Autodesk Fusion 360 part; units mm, degrees
(part 2 of 3)
ref_plane "WorkPlane161" through (-25.1, 0, 0) normal (1, 0, 0) x (0, 1, 0)
sketch "ESP service plug clearance 14 x 8 PHOTO ESTIMATE" plane through (-25.1, 0, 0) normal (1, 0, 0) x (0, 0, -1)
  line L0 (-13, -23) -> (-13, -9)
  line L1 (-13, -9) -> (-21, -9)
  line L2 (-21, -9) -> (-21, -23)
  line L3 (-21, -23) -> (-13, -23)
ref_plane "WorkPlane162" through (51.9632, 0, 0) normal (1, 0, 0) x (0, 1, 0)
sketch "Type C PCB edge slit 17.9 x 2.0 PHOTO RULER" plane through (51.9632, 0, 0) normal (1, 0, 0) x (0, 0, -1)
  line L0 (-9.3, -27.19) -> (-9.3, -9.29)
  line L1 (-9.3, -9.29) -> (-11.3, -9.29)
  line L2 (-11.3, -9.29) -> (-11.3, -27.19)
  line L3 (-11.3, -27.19) -> (-9.3, -27.19)
ref_plane "WorkPlane163" through (51.9632, 0, 0) normal (1, 0, 0) x (0, 1, 0)
sketch "Type C metal clearance 9.4 x 3.4 PHOTO RULER" plane through (51.9632, 0, 0) normal (1, 0, 0) x (0, 0, -1)
  line L0 (-6.3, -22.34) -> (-6.3, -14.14)
  line L1 (-6.3, -14.14) -> (-6.9, -13.54)
  line L2 (-6.9, -13.54) -> (-9.1, -13.54)
  line L3 (-9.1, -13.54) -> (-9.7, -14.14)
  line L4 (-9.7, -14.14) -> (-9.7, -22.34)
  line L5 (-9.7, -22.34) -> (-9.1, -22.94)
  line L6 (-9.1, -22.94) -> (-6.9, -22.94)
  line L7 (-6.9, -22.94) -> (-6.3, -22.34)
ref_plane "WorkPlane164" through (-25.1, 0, 0) normal (1, 0, 0) x (0, 1, 0)
sketch "ESP32 PCB edge slit 28.4 x 2.0 PHOTO RULER" plane through (-25.1, 0, 0) normal (1, 0, 0) x (0, 0, -1)
  line L0 (-15.9, -32.44) -> (-15.9, -4.04)
  line L1 (-15.9, -4.04) -> (-17.9, -4.04)
  line L2 (-17.9, -4.04) -> (-17.9, -32.44)
  line L3 (-17.9, -32.44) -> (-15.9, -32.44)
ref_plane "WorkPlane165" through (-25.1, 0, 0) normal (1, 0, 0) x (0, 1, 0)
sketch "ESP micro USB recessed plug access 10.4 x 4.6" plane through (-25.1, 0, 0) normal (1, 0, 0) x (0, 0, -1)
  line L0 (-16.8, -22.74) -> (-16.8, -13.74)
  line L1 (-16.8, -13.74) -> (-17.5, -13.04)
  line L2 (-17.5, -13.04) -> (-20.7, -13.04)
  line L3 (-20.7, -13.04) -> (-21.4, -13.74)
  line L4 (-21.4, -13.74) -> (-21.4, -22.74)
  line L5 (-21.4, -22.74) -> (-20.7, -23.44)
  line L6 (-20.7, -23.44) -> (-17.5, -23.44)
  line L7 (-17.5, -23.44) -> (-16.8, -22.74)
ref_plane "WorkPlane166" through (0, 0, 9.5) normal (0, 0, 1) x (1, 0, 0)
sketch "REF_DO_NOT_PRINT Charger PCB 17.5 wide PHOTO RULER" plane through (0, 0, 9.5) normal (0, 0, 1) x (1, 0, 0)
  line L0 (23.4316, -26.99) -> (50.4316, -26.99)
  line L1 (50.4316, -26.99) -> (50.4316, -9.49)
  line L2 (50.4316, -9.49) -> (23.4316, -9.49)
  line L3 (23.4316, -9.49) -> (23.4316, -26.99)
extrude "REF_DO_NOT_PRINT Charger PCB 17.5 wide PHOTO RULER (1)" add sketch "REF_DO_NOT_PRINT Charger PCB 17.5 wide PHOTO RULER" along normal blind 1.6 separate body makes body 7
ref_plane "WorkPlane167" through (0, 0, 6.5) normal (0, 0, 1) x (1, 0, 0)
sketch "REF_DO_NOT_PRINT Type C shell 9 x 3 PHOTO ESTIMATE" plane through (0, 0, 6.5) normal (0, 0, 1) x (1, 0, 0)
  line L0 (44.4316, -22.74) -> (52.4316, -22.74)
  line L1 (52.4316, -22.74) -> (52.4316, -13.74)
  line L2 (52.4316, -13.74) -> (44.4316, -13.74)
  line L3 (44.4316, -13.74) -> (44.4316, -22.74)
extrude "REF_DO_NOT_PRINT Type C shell 9 x 3 PHOTO ESTIMATE (1)" add sketch "REF_DO_NOT_PRINT Type C shell 9 x 3 PHOTO ESTIMATE" along normal blind 3 separate body makes body 8
ref_plane "WorkPlane168" through (0, 0, 16.1) normal (0, 0, 1) x (1, 0, 0)
sketch "REF_DO_NOT_PRINT ESP32 PCB 28 wide PHOTO RULER" plane through (0, 0, 16.1) normal (0, 0, 1) x (1, 0, 0)
  line L0 (-16, -32.24) -> (36, -32.24)
  line L1 (36, -32.24) -> (36, -4.24)
  line L2 (36, -4.24) -> (-16, -4.24)
  line L3 (-16, -4.24) -> (-16, -32.24)
extrude "REF_DO_NOT_PRINT ESP32 PCB 28 wide PHOTO RULER (1)" add sketch "REF_DO_NOT_PRINT ESP32 PCB 28 wide PHOTO RULER" along normal blind 1.6 separate body makes body 9
ref_plane "WorkPlane169" through (0, 0, 17.6) normal (0, 0, 1) x (1, 0, 0)
sketch "REF_DO_NOT_PRINT ESP micro USB shell 7.8 x 3 PHOTO ESTIMATE" plane through (0, 0, 17.6) normal (0, 0, 1) x (1, 0, 0)
  line L0 (-17.5, -22.14) -> (-11, -22.14)
  line L1 (-11, -22.14) -> (-11, -14.34)
  line L2 (-11, -14.34) -> (-17.5, -14.34)
  line L3 (-17.5, -14.34) -> (-17.5, -22.14)
extrude "REF_DO_NOT_PRINT ESP micro USB shell 7.8 x 3 PHOTO ESTIMATE (1)" add sketch "REF_DO_NOT_PRINT ESP micro USB shell 7.8 x 3 PHOTO ESTIMATE" along normal blind 3 separate body makes body 10
ref_plane "WorkPlane170" through (0, 0, 17.7) normal (0, 0, 1) x (1, 0, 0)
sketch "REF_DO_NOT_PRINT ESP32 shield envelope PHOTO ESTIMATE" plane through (0, 0, 17.7) normal (0, 0, 1) x (1, 0, 0)
  line L0 (4, -29.74) -> (28, -29.74)
  line L1 (28, -29.74) -> (28, -6.74)
  line L2 (28, -6.74) -> (4, -6.74)
  line L3 (4, -6.74) -> (4, -29.74)
extrude "REF_DO_NOT_PRINT ESP32 shield envelope PHOTO ESTIMATE (1)" add sketch "REF_DO_NOT_PRINT ESP32 shield envelope PHOTO ESTIMATE" along normal blind 3.8 separate body makes body 11
ref_plane "WorkPlane171" through (51.9632, 0, 0) normal (1, 0, 0) x (0, 1, 0)
sketch "Type C metal clearance 9.4 x 3.4 corner clearance" plane through (51.9632, 0, 0) normal (1, 0, 0) x (0, 0, -1)
  line L0 (-6.3, -22.64) -> (-6.3, -13.84)
  line L1 (-6.3, -13.84) -> (-6.6, -13.54)
  line L2 (-6.6, -13.54) -> (-9.4, -13.54)
  line L3 (-9.4, -13.54) -> (-9.7, -13.84)
  line L4 (-9.7, -13.84) -> (-9.7, -22.64)
  line L5 (-9.7, -22.64) -> (-9.4, -22.94)
  line L6 (-9.4, -22.94) -> (-6.6, -22.94)
  line L7 (-6.6, -22.94) -> (-6.3, -22.64)
ref_plane "WorkPlane172" through (0, 0, 27.3) normal (0, 0, 1) x (1, 0, 0)
sketch "REF_AUDIT Radio PCB 45 x 16 PHOTO APPROX" plane through (0, 0, 27.3) normal (0, 0, 1) x (1, 0, 0)
  line L0 (3.4316, 9) -> (48.4316, 9)
  line L1 (48.4316, 9) -> (48.4316, 25)
  line L2 (48.4316, 25) -> (3.4316, 25)
  line L3 (3.4316, 25) -> (3.4316, 9)
ref_plane "WorkPlane173" through (0, 0, 13.1) normal (0, 0, 1) x (1, 0, 0)
sketch "REF_AUDIT White harness connector PHOTO APPROX" plane through (0, 0, 13.1) normal (0, 0, 1) x (1, 0, 0)
  line L0 (-23.1, -22) -> (-16, -22)
  line L1 (-16, -22) -> (-16, 13)
  line L2 (-16, 13) -> (-23.1, 13)
  line L3 (-23.1, 13) -> (-23.1, -22)
ref_plane "WorkPlane174" through (0, 0, 39.1) normal (0, 0, 1) x (1, 0, 0)
sketch "Key aperture corrected layout 1" plane through (0, 0, 39.1) normal (0, 0, 1) x (1, 0, 0)
  circle A0 centre (-8, -19.5) radius 2.3
extrude "Key aperture corrected layout 1 (1)" cut sketch "Key aperture corrected layout 1" against normal blind 1.6 bodies 2
ref_plane "WorkPlane175" through (0, 0, 33.1) normal (0, 0, 1) x (1, 0, 0)
sketch "Button 1 stem layout corrected" plane through (0, 0, 33.1) normal (0, 0, 1) x (1, 0, 0)
  circle A0 centre (-8, -19.5) radius 1.6
extrude "Button 1 stem layout corrected (1)" add sketch "Button 1 stem layout corrected" along normal blind 6.4 separate body makes body 12
ref_plane "WorkPlane176" through (0, 0, 36.9) normal (0, 0, 1) x (1, 0, 0)
sketch "Button 1 retention flange (1)" plane through (0, 0, 36.9) normal (0, 0, 1) x (1, 0, 0)
  circle A0 centre (-8, -19.5) radius 2.8
extrude "Button 1 retention flange (2)" add sketch "Button 1 retention flange (1)" along normal blind 0.6 bodies 12
ref_plane "WorkPlane177" through (0, 0, 36.1) normal (0, 0, 1) x (1, 0, 0)
sketch "Button printable flange taper corrected" plane through (0, 0, 36.1) normal (0, 0, 1) x (1, 0, 0)
  circle A0 centre (-8, -19.5) radius 1.6
extrude "Button 45 degree shoulder corrected" add sketch "Button printable flange taper corrected" along normal blind 1.2 draft 45 bodies 12
ref_plane "WorkPlane178" through (0, 0, 29.6) normal (0, 0, 1) x (1, 0, 0)
sketch "REF_DO_NOT_PRINT Tact switch corrected 1" plane through (0, 0, 29.6) normal (0, 0, 1) x (1, 0, 0)
  circle A0 centre (-8, -19.5) radius 1.75
extrude "REF_DO_NOT_PRINT Tact switch corrected 1 (1)" add sketch "REF_DO_NOT_PRINT Tact switch corrected 1" along normal blind 3.5 separate body makes body 13
ref_plane "WorkPlane179" through (0, 0, 39.1) normal (0, 0, 1) x (1, 0, 0)
sketch "Key aperture corrected layout 2" plane through (0, 0, 39.1) normal (0, 0, 1) x (1, 0, 0)
  circle A0 centre (-8, -11.88) radius 2.3
extrude "Key aperture corrected layout 2 (1)" cut sketch "Key aperture corrected layout 2" against normal blind 1.6 bodies 2
ref_plane "WorkPlane180" through (0, 0, 33.1) normal (0, 0, 1) x (1, 0, 0)
sketch "Button 2 stem layout corrected" plane through (0, 0, 33.1) normal (0, 0, 1) x (1, 0, 0)
  circle A0 centre (-8, -11.88) radius 1.6
extrude "Button 2 stem layout corrected (1)" add sketch "Button 2 stem layout corrected" along normal blind 6.4 separate body makes body 14
ref_plane "WorkPlane181" through (0, 0, 36.9) normal (0, 0, 1) x (1, 0, 0)
sketch "Button 2 retention flange (1)" plane through (0, 0, 36.9) normal (0, 0, 1) x (1, 0, 0)
  circle A0 centre (-8, -11.88) radius 2.8
extrude "Button 2 retention flange (2)" add sketch "Button 2 retention flange (1)" along normal blind 0.6 bodies 14
ref_plane "WorkPlane182" through (0, 0, 36.1) normal (0, 0, 1) x (1, 0, 0)
sketch "Button printable flange taper corrected (1)" plane through (0, 0, 36.1) normal (0, 0, 1) x (1, 0, 0)
  circle A0 centre (-8, -11.88) radius 1.6
extrude "Button 45 degree shoulder corrected (1)" add sketch "Button printable flange taper corrected (1)" along normal blind 1.2 draft 45 bodies 14
ref_plane "WorkPlane183" through (0, 0, 29.6) normal (0, 0, 1) x (1, 0, 0)
sketch "REF_DO_NOT_PRINT Tact switch corrected 2" plane through (0, 0, 29.6) normal (0, 0, 1) x (1, 0, 0)
  circle A0 centre (-8, -11.88) radius 1.75
extrude "REF_DO_NOT_PRINT Tact switch corrected 2 (1)" add sketch "REF_DO_NOT_PRINT Tact switch corrected 2" along normal blind 3.5 separate body makes body 15
ref_plane "WorkPlane184" through (0, 0, 39.1) normal (0, 0, 1) x (1, 0, 0)
sketch "Key aperture corrected layout 3" plane through (0, 0, 39.1) normal (0, 0, 1) x (1, 0, 0)
  circle A0 centre (-8, -4.26) radius 2.3
extrude "Key aperture corrected layout 3 (1)" cut sketch "Key aperture corrected layout 3" against normal blind 1.6 bodies 2
ref_plane "WorkPlane185" through (0, 0, 33.1) normal (0, 0, 1) x (1, 0, 0)
sketch "Button 3 stem layout corrected" plane through (0, 0, 33.1) normal (0, 0, 1) x (1, 0, 0)
  circle A0 centre (-8, -4.26) radius 1.6
extrude "Button 3 stem layout corrected (1)" add sketch "Button 3 stem layout corrected" along normal blind 6.4 separate body makes body 16
ref_plane "WorkPlane186" through (0, 0, 36.9) normal (0, 0, 1) x (1, 0, 0)
sketch "Button 3 retention flange (1)" plane through (0, 0, 36.9) normal (0, 0, 1) x (1, 0, 0)
  circle A0 centre (-8, -4.26) radius 2.8
extrude "Button 3 retention flange (2)" add sketch "Button 3 retention flange (1)" along normal blind 0.6 bodies 16
ref_plane "WorkPlane187" through (0, 0, 36.1) normal (0, 0, 1) x (1, 0, 0)
sketch "Button printable flange taper corrected (2)" plane through (0, 0, 36.1) normal (0, 0, 1) x (1, 0, 0)
  circle A0 centre (-8, -4.26) radius 1.6
extrude "Button 45 degree shoulder corrected (2)" add sketch "Button printable flange taper corrected (2)" along normal blind 1.2 draft 45 bodies 16
ref_plane "WorkPlane188" through (0, 0, 29.6) normal (0, 0, 1) x (1, 0, 0)
sketch "REF_DO_NOT_PRINT Tact switch corrected 3" plane through (0, 0, 29.6) normal (0, 0, 1) x (1, 0, 0)
  circle A0 centre (-8, -4.26) radius 1.75
extrude "REF_DO_NOT_PRINT Tact switch corrected 3 (1)" add sketch "REF_DO_NOT_PRINT Tact switch corrected 3" along normal blind 3.5 separate body makes body 17
ref_plane "WorkPlane189" through (0, 0, 39.1) normal (0, 0, 1) x (1, 0, 0)
sketch "Key aperture corrected layout 4" plane through (0, 0, 39.1) normal (0, 0, 1) x (1, 0, 0)
  circle A0 centre (-8, 3.36) radius 2.3
extrude "Key aperture corrected layout 4 (1)" cut sketch "Key aperture corrected layout 4" against normal blind 1.6 bodies 2
ref_plane "WorkPlane190" through (0, 0, 33.1) normal (0, 0, 1) x (1, 0, 0)
sketch "Button 4 stem layout corrected" plane through (0, 0, 33.1) normal (0, 0, 1) x (1, 0, 0)
  circle A0 centre (-8, 3.36) radius 1.6
extrude "Button 4 stem layout corrected (1)" add sketch "Button 4 stem layout corrected" along normal blind 6.4 separate body makes body 18
ref_plane "WorkPlane191" through (0, 0, 36.9) normal (0, 0, 1) x (1, 0, 0)
sketch "Button 4 retention flange (1)" plane through (0, 0, 36.9) normal (0, 0, 1) x (1, 0, 0)
  circle A0 centre (-8, 3.36) radius 2.8
extrude "Button 4 retention flange (2)" add sketch "Button 4 retention flange (1)" along normal blind 0.6 bodies 18
ref_plane "WorkPlane192" through (0, 0, 36.1) normal (0, 0, 1) x (1, 0, 0)
sketch "Button printable flange taper corrected (3)" plane through (0, 0, 36.1) normal (0, 0, 1) x (1, 0, 0)
  circle A0 centre (-8, 3.36) radius 1.6
extrude "Button 45 degree shoulder corrected (3)" add sketch "Button printable flange taper corrected (3)" along normal blind 1.2 draft 45 bodies 18
ref_plane "WorkPlane193" through (0, 0, 29.6) normal (0, 0, 1) x (1, 0, 0)
sketch "REF_DO_NOT_PRINT Tact switch corrected 4" plane through (0, 0, 29.6) normal (0, 0, 1) x (1, 0, 0)
  circle A0 centre (-8, 3.36) radius 1.75
extrude "REF_DO_NOT_PRINT Tact switch corrected 4 (1)" add sketch "REF_DO_NOT_PRINT Tact switch corrected 4" along normal blind 3.5 separate body makes body 19
ref_plane "WorkPlane194" through (0, 0, 39.1) normal (0, 0, 1) x (1, 0, 0)
sketch "Key aperture corrected layout 5" plane through (0, 0, 39.1) normal (0, 0, 1) x (1, 0, 0)
  circle A0 centre (-0.38, -19.5) radius 2.3
extrude "Key aperture corrected layout 5 (1)" cut sketch "Key aperture corrected layout 5" against normal blind 1.6 bodies 2
ref_plane "WorkPlane195" through (0, 0, 33.1) normal (0, 0, 1) x (1, 0, 0)
sketch "Button 5 stem layout corrected" plane through (0, 0, 33.1) normal (0, 0, 1) x (1, 0, 0)
  circle A0 centre (-0.38, -19.5) radius 1.6
extrude "Button 5 stem layout corrected (1)" add sketch "Button 5 stem layout corrected" along normal blind 6.4 separate body makes body 20
ref_plane "WorkPlane196" through (0, 0, 36.9) normal (0, 0, 1) x (1, 0, 0)
sketch "Button 5 retention flange (1)" plane through (0, 0, 36.9) normal (0, 0, 1) x (1, 0, 0)
  circle A0 centre (-0.38, -19.5) radius 2.8
extrude "Button 5 retention flange (2)" add sketch "Button 5 retention flange (1)" along normal blind 0.6 bodies 20
ref_plane "WorkPlane197" through (0, 0, 36.1) normal (0, 0, 1) x (1, 0, 0)
sketch "Button printable flange taper corrected (4)" plane through (0, 0, 36.1) normal (0, 0, 1) x (1, 0, 0)
  circle A0 centre (-0.38, -19.5) radius 1.6
extrude "Button 45 degree shoulder corrected (4)" add sketch "Button printable flange taper corrected (4)" along normal blind 1.2 draft 45 bodies 20
ref_plane "WorkPlane198" through (0, 0, 29.6) normal (0, 0, 1) x (1, 0, 0)
sketch "REF_DO_NOT_PRINT Tact switch corrected 5" plane through (0, 0, 29.6) normal (0, 0, 1) x (1, 0, 0)
  circle A0 centre (-0.38, -19.5) radius 1.75
extrude "REF_DO_NOT_PRINT Tact switch corrected 5 (1)" add sketch "REF_DO_NOT_PRINT Tact switch corrected 5" along normal blind 3.5 separate body makes body 21
ref_plane "WorkPlane199" through (0, 0, 39.1) normal (0, 0, 1) x (1, 0, 0)
sketch "Key aperture corrected layout 6" plane through (0, 0, 39.1) normal (0, 0, 1) x (1, 0, 0)
  circle A0 centre (-0.38, -11.88) radius 2.3
extrude "Key aperture corrected layout 6 (1)" cut sketch "Key aperture corrected layout 6" against normal blind 1.6 bodies 2
ref_plane "WorkPlane200" through (0, 0, 33.1) normal (0, 0, 1) x (1, 0, 0)
sketch "Button 6 stem layout corrected" plane through (0, 0, 33.1) normal (0, 0, 1) x (1, 0, 0)
  circle A0 centre (-0.38, -11.88) radius 1.6
extrude "Button 6 stem layout corrected (1)" add sketch "Button 6 stem layout corrected" along normal blind 6.4 separate body makes body 22
ref_plane "WorkPlane201" through (0, 0, 36.9) normal (0, 0, 1) x (1, 0, 0)
sketch "Button 6 retention flange (1)" plane through (0, 0, 36.9) normal (0, 0, 1) x (1, 0, 0)
  circle A0 centre (-0.38, -11.88) radius 2.8
extrude "Button 6 retention flange (2)" add sketch "Button 6 retention flange (1)" along normal blind 0.6 bodies 22
ref_plane "WorkPlane202" through (0, 0, 36.1) normal (0, 0, 1) x (1, 0, 0)
sketch "Button printable flange taper corrected (5)" plane through (0, 0, 36.1) normal (0, 0, 1) x (1, 0, 0)
  circle A0 centre (-0.38, -11.88) radius 1.6
extrude "Button 45 degree shoulder corrected (5)" add sketch "Button printable flange taper corrected (5)" along normal blind 1.2 draft 45 bodies 22
ref_plane "WorkPlane203" through (0, 0, 29.6) normal (0, 0, 1) x (1, 0, 0)
sketch "REF_DO_NOT_PRINT Tact switch corrected 6" plane through (0, 0, 29.6) normal (0, 0, 1) x (1, 0, 0)
  circle A0 centre (-0.38, -11.88) radius 1.75
extrude "REF_DO_NOT_PRINT Tact switch corrected 6 (1)" add sketch "REF_DO_NOT_PRINT Tact switch corrected 6" along normal blind 3.5 separate body makes body 23
ref_plane "WorkPlane204" through (0, 0, 39.1) normal (0, 0, 1) x (1, 0, 0)
sketch "Key aperture corrected layout 7" plane through (0, 0, 39.1) normal (0, 0, 1) x (1, 0, 0)
  circle A0 centre (-0.38, -4.26) radius 2.3
extrude "Key aperture corrected layout 7 (1)" cut sketch "Key aperture corrected layout 7" against normal blind 1.6 bodies 2
ref_plane "WorkPlane205" through (0, 0, 33.1) normal (0, 0, 1) x (1, 0, 0)
sketch "Button 7 stem layout corrected" plane through (0, 0, 33.1) normal (0, 0, 1) x (1, 0, 0)
  circle A0 centre (-0.38, -4.26) radius 1.6
extrude "Button 7 stem layout corrected (1)" add sketch "Button 7 stem layout corrected" along normal blind 6.4 separate body makes body 24
ref_plane "WorkPlane206" through (0, 0, 36.9) normal (0, 0, 1) x (1, 0, 0)
sketch "Button 7 retention flange (1)" plane through (0, 0, 36.9) normal (0, 0, 1) x (1, 0, 0)
  circle A0 centre (-0.38, -4.26) radius 2.8
extrude "Button 7 retention flange (2)" add sketch "Button 7 retention flange (1)" along normal blind 0.6 bodies 24
ref_plane "WorkPlane207" through (0, 0, 36.1) normal (0, 0, 1) x (1, 0, 0)
sketch "Button printable flange taper corrected (6)" plane through (0, 0, 36.1) normal (0, 0, 1) x (1, 0, 0)
  circle A0 centre (-0.38, -4.26) radius 1.6
extrude "Button 45 degree shoulder corrected (6)" add sketch "Button printable flange taper corrected (6)" along normal blind 1.2 draft 45 bodies 24
ref_plane "WorkPlane208" through (0, 0, 29.6) normal (0, 0, 1) x (1, 0, 0)
sketch "REF_DO_NOT_PRINT Tact switch corrected 7" plane through (0, 0, 29.6) normal (0, 0, 1) x (1, 0, 0)
  circle A0 centre (-0.38, -4.26) radius 1.75
extrude "REF_DO_NOT_PRINT Tact switch corrected 7 (1)" add sketch "REF_DO_NOT_PRINT Tact switch corrected 7" along normal blind 3.5 separate body makes body 25
ref_plane "WorkPlane209" through (0, 0, 39.1) normal (0, 0, 1) x (1, 0, 0)
sketch "Key aperture corrected layout 8" plane through (0, 0, 39.1) normal (0, 0, 1) x (1, 0, 0)
  circle A0 centre (-0.38, 3.36) radius 2.3
extrude "Key aperture corrected layout 8 (1)" cut sketch "Key aperture corrected layout 8" against normal blind 1.6 bodies 2
ref_plane "WorkPlane210" through (0, 0, 33.1) normal (0, 0, 1) x (1, 0, 0)
sketch "Button 8 stem layout corrected" plane through (0, 0, 33.1) normal (0, 0, 1) x (1, 0, 0)
  circle A0 centre (-0.38, 3.36) radius 1.6
extrude "Button 8 stem layout corrected (1)" add sketch "Button 8 stem layout corrected" along normal blind 6.4 separate body makes body 26
ref_plane "WorkPlane211" through (0, 0, 36.9) normal (0, 0, 1) x (1, 0, 0)
sketch "Button 8 retention flange (1)" plane through (0, 0, 36.9) normal (0, 0, 1) x (1, 0, 0)
  circle A0 centre (-0.38, 3.36) radius 2.8
extrude "Button 8 retention flange (2)" add sketch "Button 8 retention flange (1)" along normal blind 0.6 bodies 26
ref_plane "WorkPlane212" through (0, 0, 36.1) normal (0, 0, 1) x (1, 0, 0)
sketch "Button printable flange taper corrected (7)" plane through (0, 0, 36.1) normal (0, 0, 1) x (1, 0, 0)
  circle A0 centre (-0.38, 3.36) radius 1.6
extrude "Button 45 degree shoulder corrected (7)" add sketch "Button printable flange taper corrected (7)" along normal blind 1.2 draft 45 bodies 26
ref_plane "WorkPlane213" through (0, 0, 29.6) normal (0, 0, 1) x (1, 0, 0)
sketch "REF_DO_NOT_PRINT Tact switch corrected 8" plane through (0, 0, 29.6) normal (0, 0, 1) x (1, 0, 0)
  circle A0 centre (-0.38, 3.36) radius 1.75
extrude "REF_DO_NOT_PRINT Tact switch corrected 8 (1)" add sketch "REF_DO_NOT_PRINT Tact switch corrected 8" along normal blind 3.5 separate body makes body 27
ref_plane "WorkPlane214" through (0, 0, 39.1) normal (0, 0, 1) x (1, 0, 0)
sketch "LED aperture corrected 5.08 pitch 1 PHOTO" plane through (0, 0, 39.1) normal (0, 0, 1) x (1, 0, 0)
  circle A0 centre (9, -15.96) radius 2.7
ref_plane "WorkPlane215" through (0, 0, 29.6) normal (0, 0, 1) x (1, 0, 0)
sketch "REF_DO_NOT_PRINT LED corrected 1 PHOTO" plane through (0, 0, 29.6) normal (0, 0, 1) x (1, 0, 0)
  circle A0 centre (9, -15.96) radius 2.5
ref_plane "WorkPlane216" through (0, 0, 39.1) normal (0, 0, 1) x (1, 0, 0)
sketch "LED aperture corrected 5.08 pitch 2 PHOTO" plane through (0, 0, 39.1) normal (0, 0, 1) x (1, 0, 0)
  circle A0 centre (9, -10.88) radius 2.7
ref_plane "WorkPlane217" through (0, 0, 29.6) normal (0, 0, 1) x (1, 0, 0)
sketch "REF_DO_NOT_PRINT LED corrected 2 PHOTO" plane through (0, 0, 29.6) normal (0, 0, 1) x (1, 0, 0)
  circle A0 centre (9, -10.88) radius 2.5
ref_plane "WorkPlane218" through (0, 0, 39.1) normal (0, 0, 1) x (1, 0, 0)
sketch "LED aperture corrected 5.08 pitch 3 PHOTO" plane through (0, 0, 39.1) normal (0, 0, 1) x (1, 0, 0)
  circle A0 centre (9, -5.8) radius 2.7
ref_plane "WorkPlane219" through (0, 0, 29.6) normal (0, 0, 1) x (1, 0, 0)
sketch "REF_DO_NOT_PRINT LED corrected 3 PHOTO" plane through (0, 0, 29.6) normal (0, 0, 1) x (1, 0, 0)
  circle A0 centre (9, -5.8) radius 2.5
ref_plane "WorkPlane220" through (0, 0, 28) normal (0, 0, 1) x (1, 0, 0)
sketch "REF_DO_NOT_PRINT Keypad PCB moved 2.5 mm right PHOTO" plane through (0, 0, 28) normal (0, 0, 1) x (1, 0, 0)
  line L0 (-14, -24.5) -> (15, -24.5)
  line L1 (15, -24.5) -> (15, 7.5)
  line L2 (15, 7.5) -> (-14, 7.5)
  line L3 (-14, 7.5) -> (-14, -24.5)
extrude "REF_DO_NOT_PRINT Keypad PCB moved 2.5 mm right PHOTO (1)" add sketch "REF_DO_NOT_PRINT Keypad PCB moved 2.5 mm right PHOTO" along normal blind 1.6 separate body makes body 28
ref_plane "WorkPlane221" through (0, 0, 27.2) normal (0, 0, 1) x (1, 0, 0)
sketch "Keypad flexible edge finger corrected" plane through (0, 0, 27.2) normal (0, 0, 1) x (1, 0, 0)
  line L0 (-13, -25.6) -> (-9, -25.6)
  line L1 (-9, -25.6) -> (-9, -24.8)
  line L2 (-9, -24.8) -> (-13, -24.8)
  line L3 (-13, -24.8) -> (-13, -25.6)
extrude "Keypad flexible edge finger corrected (1)" add sketch "Keypad flexible edge finger corrected" along normal blind 10.8 bodies 2
ref_plane "WorkPlane222" through (0, 0, 27.2) normal (0, 0, 1) x (1, 0, 0)
sketch "Keypad lower capture shelf corrected" plane through (0, 0, 27.2) normal (0, 0, 1) x (1, 0, 0)
  line L0 (-13, -25.6) -> (-9, -25.6)
  line L1 (-9, -25.6) -> (-9, -23.8)
  line L2 (-9, -23.8) -> (-13, -23.8)
  line L3 (-13, -23.8) -> (-13, -25.6)
extrude "Keypad lower capture shelf corrected (1)" add sketch "Keypad lower capture shelf corrected" along normal blind 0.7 bodies 2
ref_plane "WorkPlane223" through (0, 0, 29.7) normal (0, 0, 1) x (1, 0, 0)
sketch "Keypad upper spacer corrected" plane through (0, 0, 29.7) normal (0, 0, 1) x (1, 0, 0)
  line L0 (-12, -24.5) -> (-10, -24.5)
  line L1 (-10, -24.5) -> (-10, -23.5)
  line L2 (-10, -23.5) -> (-12, -23.5)
  line L3 (-12, -23.5) -> (-12, -24.5)
extrude "Keypad upper spacer corrected (1)" add sketch "Keypad upper spacer corrected" along normal blind 8.3 bodies 2
ref_plane "WorkPlane224" through (0, 0, 27.2) normal (0, 0, 1) x (1, 0, 0)
sketch "Keypad flexible edge finger corrected (1)" plane through (0, 0, 27.2) normal (0, 0, 1) x (1, 0, 0)
  line L0 (-13, 7.8) -> (-9, 7.8)
  line L1 (-9, 7.8) -> (-9, 8.6)
  line L2 (-9, 8.6) -> (-13, 8.6)
  line L3 (-13, 8.6) -> (-13, 7.8)
extrude "Keypad flexible edge finger corrected (2)" add sketch "Keypad flexible edge finger corrected (1)" along normal blind 10.8 bodies 2
ref_plane "WorkPlane225" through (0, 0, 27.2) normal (0, 0, 1) x (1, 0, 0)
sketch "Keypad lower capture shelf corrected (1)" plane through (0, 0, 27.2) normal (0, 0, 1) x (1, 0, 0)
  line L0 (-13, 6.8) -> (-9, 6.8)
  line L1 (-9, 6.8) -> (-9, 8.6)
  line L2 (-9, 8.6) -> (-13, 8.6)
  line L3 (-13, 8.6) -> (-13, 6.8)
extrude "Keypad lower capture shelf corrected (2)" add sketch "Keypad lower capture shelf corrected (1)" along normal blind 0.7 bodies 2
ref_plane "WorkPlane226" through (0, 0, 29.7) normal (0, 0, 1) x (1, 0, 0)
sketch "Keypad upper spacer corrected (1)" plane through (0, 0, 29.7) normal (0, 0, 1) x (1, 0, 0)
  line L0 (-12, 6.5) -> (-10, 6.5)
  line L1 (-10, 6.5) -> (-10, 7.5)
  line L2 (-10, 7.5) -> (-12, 7.5)
  line L3 (-12, 7.5) -> (-12, 6.5)
extrude "Keypad upper spacer corrected (2)" add sketch "Keypad upper spacer corrected (1)" along normal blind 8.3 bodies 2
ref_plane "WorkPlane227" through (0, 0, 27.2) normal (0, 0, 1) x (1, 0, 0)
sketch "Keypad flexible edge finger corrected (2)" plane through (0, 0, 27.2) normal (0, 0, 1) x (1, 0, 0)
  line L0 (10, -25.6) -> (14, -25.6)
  line L1 (14, -25.6) -> (14, -24.8)
  line L2 (14, -24.8) -> (10, -24.8)
  line L3 (10, -24.8) -> (10, -25.6)
extrude "Keypad flexible edge finger corrected (3)" add sketch "Keypad flexible edge finger corrected (2)" along normal blind 10.8 bodies 2
ref_plane "WorkPlane228" through (0, 0, 27.2) normal (0, 0, 1) x (1, 0, 0)
sketch "Keypad lower capture shelf corrected (2)" plane through (0, 0, 27.2) normal (0, 0, 1) x (1, 0, 0)
  line L0 (10, -25.6) -> (14, -25.6)
  line L1 (14, -25.6) -> (14, -23.8)
  line L2 (14, -23.8) -> (10, -23.8)
  line L3 (10, -23.8) -> (10, -25.6)
extrude "Keypad lower capture shelf corrected (3)" add sketch "Keypad lower capture shelf corrected (2)" along normal blind 0.7 bodies 2
ref_plane "WorkPlane229" through (0, 0, 29.7) normal (0, 0, 1) x (1, 0, 0)
sketch "Keypad upper spacer corrected (2)" plane through (0, 0, 29.7) normal (0, 0, 1) x (1, 0, 0)
  line L0 (11, -24.5) -> (13, -24.5)
  line L1 (13, -24.5) -> (13, -23.5)
  line L2 (13, -23.5) -> (11, -23.5)
  line L3 (11, -23.5) -> (11, -24.5)
extrude "Keypad upper spacer corrected (3)" add sketch "Keypad upper spacer corrected (2)" along normal blind 8.3 bodies 2
ref_plane "WorkPlane230" through (0, 0, 27.2) normal (0, 0, 1) x (1, 0, 0)
sketch "Keypad flexible edge finger corrected (3)" plane through (0, 0, 27.2) normal (0, 0, 1) x (1, 0, 0)
  line L0 (10, 7.8) -> (14, 7.8)
  line L1 (14, 7.8) -> (14, 8.6)
  line L2 (14, 8.6) -> (10, 8.6)
  line L3 (10, 8.6) -> (10, 7.8)
extrude "Keypad flexible edge finger corrected (4)" add sketch "Keypad flexible edge finger corrected (3)" along normal blind 10.8 bodies 2
ref_plane "WorkPlane231" through (0, 0, 27.2) normal (0, 0, 1) x (1, 0, 0)
sketch "Keypad lower capture shelf corrected (3)" plane through (0, 0, 27.2) normal (0, 0, 1) x (1, 0, 0)
  line L0 (10, 6.8) -> (14, 6.8)
  line L1 (14, 6.8) -> (14, 8.6)
  line L2 (14, 8.6) -> (10, 8.6)
  line L3 (10, 8.6) -> (10, 6.8)
extrude "Keypad lower capture shelf corrected (4)" add sketch "Keypad lower capture shelf corrected (3)" along normal blind 0.7 bodies 2
ref_plane "WorkPlane232" through (0, 0, 29.7) normal (0, 0, 1) x (1, 0, 0)
sketch "Keypad upper spacer corrected (3)" plane through (0, 0, 29.7) normal (0, 0, 1) x (1, 0, 0)
  line L0 (11, 6.5) -> (13, 6.5)
  line L1 (13, 6.5) -> (13, 7.5)
  line L2 (13, 7.5) -> (11, 7.5)
  line L3 (11, 7.5) -> (11, 6.5)
extrude "Keypad upper spacer corrected (4)" add sketch "Keypad upper spacer corrected (3)" along normal blind 8.3 bodies 2
ref_plane "WorkPlane233" through (0, 0, 39.1) normal (0, 0, 1) x (1, 0, 0)
sketch "Buzzer vent right side corrected 0" plane through (0, 0, 39.1) normal (0, 0, 1) x (1, 0, 0)
  circle A0 centre (-17.3, -30.3) radius 0.75
extrude "Buzzer vent right side corrected 0 (1)" cut sketch "Buzzer vent right side corrected 0" against normal blind 1.6 bodies 2
ref_plane "WorkPlane234" through (0, 0, 39.1) normal (0, 0, 1) x (1, 0, 0)
sketch "Buzzer vent right side corrected 1" plane through (0, 0, 39.1) normal (0, 0, 1) x (1, 0, 0)
  circle A0 centre (-14.8, -30.3) radius 0.75
extrude "Buzzer vent right side corrected 1 (1)" cut sketch "Buzzer vent right side corrected 1" against normal blind 1.6 bodies 2
ref_plane "WorkPlane235" through (0, 0, 39.1) normal (0, 0, 1) x (1, 0, 0)
sketch "Buzzer vent right side corrected 2" plane through (0, 0, 39.1) normal (0, 0, 1) x (1, 0, 0)
  circle A0 centre (-19.8, -30.3) radius 0.75
extrude "Buzzer vent right side corrected 2 (1)" cut sketch "Buzzer vent right side corrected 2" against normal blind 1.6 bodies 2
ref_plane "WorkPlane236" through (0, 0, 39.1) normal (0, 0, 1) x (1, 0, 0)
sketch "Buzzer vent right side corrected 3" plane through (0, 0, 39.1) normal (0, 0, 1) x (1, 0, 0)
  circle A0 centre (-17.3, -27.8) radius 0.75
extrude "Buzzer vent right side corrected 3 (1)" cut sketch "Buzzer vent right side corrected 3" against normal blind 1.6 bodies 2
ref_plane "WorkPlane237" through (0, 0, 39.1) normal (0, 0, 1) x (1, 0, 0)
sketch "Buzzer vent right side corrected 4" plane through (0, 0, 39.1) normal (0, 0, 1) x (1, 0, 0)
  circle A0 centre (-17.3, -32.8) radius 0.75
extrude "Buzzer vent right side corrected 4 (1)" cut sketch "Buzzer vent right side corrected 4" against normal blind 1.6 bodies 2
ref_plane "WorkPlane238" through (0, 0, 23.1) normal (0, 0, 1) x (1, 0, 0)
sketch "REF_DO_NOT_PRINT Buzzer right lower corner PHOTO" plane through (0, 0, 23.1) normal (0, 0, 1) x (1, 0, 0)
  circle A0 centre (-17.3, -30.3) radius 6
extrude "REF_DO_NOT_PRINT Buzzer right lower corner PHOTO (1)" add sketch "REF_DO_NOT_PRINT Buzzer right lower corner PHOTO" along normal blind 10 separate body makes body 29
ref_plane "WorkPlane239" through (0, 0, 27.3) normal (0, 0, 1) x (1, 0, 0)
sketch "REF_DO_NOT_PRINT Radio PCB 45 x 16 PHOTO APPROX" plane through (0, 0, 27.3) normal (0, 0, 1) x (1, 0, 0)
  line L0 (3.4316, 9) -> (48.4316, 9)
  line L1 (48.4316, 9) -> (48.4316, 25)
  line L2 (48.4316, 25) -> (3.4316, 25)
  line L3 (3.4316, 25) -> (3.4316, 9)
extrude "REF_DO_NOT_PRINT Radio PCB 45 x 16 PHOTO APPROX (1)" add sketch "REF_DO_NOT_PRINT Radio PCB 45 x 16 PHOTO APPROX" along normal blind 2 separate body makes body 30
ref_plane "WorkPlane240" through (0, 0, 13.1) normal (0, 0, 1) x (1, 0, 0)
sketch "REF_DO_NOT_PRINT White harness connector PHOTO APPROX" plane through (0, 0, 13.1) normal (0, 0, 1) x (1, 0, 0)
  line L0 (-23.1, -13.8) -> (-16, -13.8)
  line L1 (-16, -13.8) -> (-16, 22.2)
  line L2 (-16, 22.2) -> (-23.1, 22.2)
  line L3 (-23.1, 22.2) -> (-23.1, -13.8)
extrude "REF_DO_NOT_PRINT White harness connector PHOTO APPROX (1)" add sketch "REF_DO_NOT_PRINT White harness connector PHOTO APPROX" along normal blind 10 separate body makes body 31
ref_plane "WorkPlane241" through (0, 0, 39.1) normal (0, 0, 1) x (1, 0, 0)
sketch "LED 3.4 mm aperture 5.08 pitch PHOTO 1" plane through (0, 0, 39.1) normal (0, 0, 1) x (1, 0, 0)
  circle A0 centre (9, -15.96) radius 1.7
extrude "LED 3.4 mm aperture 5.08 pitch PHOTO 1 (1)" cut sketch "LED 3.4 mm aperture 5.08 pitch PHOTO 1" against normal blind 1.6 bodies 2
ref_plane "WorkPlane242" through (0, 0, 29.6) normal (0, 0, 1) x (1, 0, 0)
sketch "REF_DO_NOT_PRINT LED 3 mm PHOTO 1" plane through (0, 0, 29.6) normal (0, 0, 1) x (1, 0, 0)
  circle A0 centre (9, -15.96) radius 1.5
extrude "REF_DO_NOT_PRINT LED 3 mm PHOTO 1 (1)" add sketch "REF_DO_NOT_PRINT LED 3 mm PHOTO 1" along normal blind 7.3 separate body makes body 32
ref_plane "WorkPlane243" through (0, 0, 39.1) normal (0, 0, 1) x (1, 0, 0)
sketch "LED 3.4 mm aperture 5.08 pitch PHOTO 2" plane through (0, 0, 39.1) normal (0, 0, 1) x (1, 0, 0)
  circle A0 centre (9, -10.88) radius 1.7
extrude "LED 3.4 mm aperture 5.08 pitch PHOTO 2 (1)" cut sketch "LED 3.4 mm aperture 5.08 pitch PHOTO 2" against normal blind 1.6 bodies 2
ref_plane "WorkPlane244" through (0, 0, 29.6) normal (0, 0, 1) x (1, 0, 0)
sketch "REF_DO_NOT_PRINT LED 3 mm PHOTO 2" plane through (0, 0, 29.6) normal (0, 0, 1) x (1, 0, 0)
  circle A0 centre (9, -10.88) radius 1.5
extrude "REF_DO_NOT_PRINT LED 3 mm PHOTO 2 (1)" add sketch "REF_DO_NOT_PRINT LED 3 mm PHOTO 2" along normal blind 7.3 separate body makes body 33
ref_plane "WorkPlane245" through (0, 0, 39.1) normal (0, 0, 1) x (1, 0, 0)
sketch "LED 3.4 mm aperture 5.08 pitch PHOTO 3" plane through (0, 0, 39.1) normal (0, 0, 1) x (1, 0, 0)
  circle A0 centre (9, -5.8) radius 1.7
extrude "LED 3.4 mm aperture 5.08 pitch PHOTO 3 (1)" cut sketch "LED 3.4 mm aperture 5.08 pitch PHOTO 3" against normal blind 1.6 bodies 2
ref_plane "WorkPlane246" through (0, 0, 29.6) normal (0, 0, 1) x (1, 0, 0)
sketch "REF_DO_NOT_PRINT LED 3 mm PHOTO 3" plane through (0, 0, 29.6) normal (0, 0, 1) x (1, 0, 0)
  circle A0 centre (9, -5.8) radius 1.5
extrude "REF_DO_NOT_PRINT LED 3 mm PHOTO 3 (1)" add sketch "REF_DO_NOT_PRINT LED 3 mm PHOTO 3" along normal blind 7.3 separate body makes body 34
ref_plane "WorkPlane247" through (0, 0, -2) normal (0, 0, 1) x (1, 0, 0)
sketch "REF_DO_NOT_PRINT DC DC below main PCB USER says thinner than battery" plane through (0, 0, -2) normal (0, 0, 1) x (1, 0, 0)
  line L0 (16, -26) -> (37, -26)
  line L1 (37, -26) -> (37, 17)
  line L2 (37, 17) -> (16, 17)
  line L3 (16, 17) -> (16, -26)
ref_plane "WorkPlane248" through (51.5, 0, 0) normal (1, 0, 0) x (0, 1, 0)
sketch "SMA neat collar housing" plane through (51.5, 0, 0) normal (1, 0, 0) x (0, 0, -1)
  arc A0 (-34, 12.6514) -> (-34, 21.3486) centre (-32.5, 17) ccw
  line L0 (-34, 21.3486) -> (-34, 12.6514)
ref_plane "WorkPlane249" through (51.5, 0, 0) normal (1, 0, 0) x (0, 1, 0)
sketch "SMA neat collar lid" plane through (51.5, 0, 0) normal (1, 0, 0) x (0, 0, -1)
  arc A0 (-34, 21.3486) -> (-34, 12.6514) centre (-32.5, 17) ccw
  line L0 (-34, 21.3486) -> (-34, 12.6514)
ref_plane "WorkPlane250" through (52.5316, 0, 0) normal (1, 0, 0) x (0, 1, 0)
sketch "SMA 6.8 mm round clearance housing" plane through (52.5316, 0, 0) normal (1, 0, 0) x (0, 0, -1)
  circle A0 centre (-32.5, 17) radius 3.4
ref_plane "WorkPlane251" through (52.5316, 0, 0) normal (1, 0, 0) x (0, 1, 0)
sketch "SMA 6.8 mm round clearance lid" plane through (52.5316, 0, 0) normal (1, 0, 0) x (0, 0, -1)
  circle A0 centre (-32.5, 17) radius 3.4
ref_plane "WorkPlane252" through (0, 0, 39.1) normal (0, 0, 1) x (1, 0, 0)
sketch "OLED flush face opening 30.4 x 16.4 PHOTO" plane through (0, 0, 39.1) normal (0, 0, 1) x (1, 0, 0)
  line L0 (24.8, -20.7) -> (41.2, -20.7)
  line L1 (41.2, -20.7) -> (41.2, 9.7)
  line L2 (41.2, 9.7) -> (24.8, 9.7)
  line L3 (24.8, 9.7) -> (24.8, -20.7)
ref_plane "WorkPlane253" through (0, 0, 34.5) normal (0, 0, 1) x (1, 0, 0)
sketch "REF_DO_NOT_PRINT OLED PCB flush seating PHOTO" plane through (0, 0, 34.5) normal (0, 0, 1) x (1, 0, 0)
  line L0 (16.25, -23.25) -> (49.75, -23.25)
  line L1 (49.75, -23.25) -> (49.75, 12.25)
  line L2 (49.75, 12.25) -> (16.25, 12.25)
  line L3 (16.25, 12.25) -> (16.25, -23.25)
ref_plane "WorkPlane254" through (0, 0, 36.1) normal (0, 0, 1) x (1, 0, 0)
sketch "REF_DO_NOT_PRINT OLED glass face flush with lid PHOTO" plane through (0, 0, 36.1) normal (0, 0, 1) x (1, 0, 0)
  line L0 (25, -20.5) -> (41, -20.5)
  line L1 (41, -20.5) -> (41, 9.5)
  line L2 (41, 9.5) -> (25, 9.5)
  line L3 (25, 9.5) -> (25, -20.5)
ref_plane "WorkPlane255" through (0, 0, 33.7) normal (0, 0, 1) x (1, 0, 0)
sketch "OLED flush flexible holder 0.6 PETG" plane through (0, 0, 33.7) normal (0, 0, 1) x (1, 0, 0)
  line L0 (16.5, -24.15) -> (20.5, -24.15)
  line L1 (20.5, -24.15) -> (20.5, -23.55)
  line L2 (20.5, -23.55) -> (16.5, -23.55)
  line L3 (16.5, -23.55) -> (16.5, -24.15)
ref_plane "WorkPlane256" through (0, 0, 33.8) normal (0, 0, 1) x (1, 0, 0)
sketch "OLED flush lower capture ledge" plane through (0, 0, 33.8) normal (0, 0, 1) x (1, 0, 0)
  line L0 (16.5, -24.15) -> (20.5, -24.15)
  line L1 (20.5, -24.15) -> (20.5, -22.95)
  line L2 (20.5, -22.95) -> (16.5, -22.95)
  line L3 (16.5, -22.95) -> (16.5, -24.15)
ref_plane "WorkPlane257" through (0, 0, 36.2) normal (0, 0, 1) x (1, 0, 0)
sketch "OLED flush upper datum spacer" plane through (0, 0, 36.2) normal (0, 0, 1) x (1, 0, 0)
  line L0 (17.5, -23.25) -> (19.5, -23.25)
  line L1 (19.5, -23.25) -> (19.5, -22.55)
  line L2 (19.5, -22.55) -> (17.5, -22.55)
  line L3 (17.5, -22.55) -> (17.5, -23.25)
ref_plane "WorkPlane258" through (0, 0, 33.7) normal (0, 0, 1) x (1, 0, 0)
sketch "OLED flush flexible holder 0.6 PETG (1)" plane through (0, 0, 33.7) normal (0, 0, 1) x (1, 0, 0)
  line L0 (16.5, 12.55) -> (20.5, 12.55)
  line L1 (20.5, 12.55) -> (20.5, 13.15)
  line L2 (20.5, 13.15) -> (16.5, 13.15)
  line L3 (16.5, 13.15) -> (16.5, 12.55)
ref_plane "WorkPlane259" through (0, 0, 33.8) normal (0, 0, 1) x (1, 0, 0)
sketch "OLED flush lower capture ledge (1)" plane through (0, 0, 33.8) normal (0, 0, 1) x (1, 0, 0)
  line L0 (16.5, 11.95) -> (20.5, 11.95)
  line L1 (20.5, 11.95) -> (20.5, 13.15)
  line L2 (20.5, 13.15) -> (16.5, 13.15)
  line L3 (16.5, 13.15) -> (16.5, 11.95)
ref_plane "WorkPlane260" through (0, 0, 36.2) normal (0, 0, 1) x (1, 0, 0)
sketch "OLED flush upper datum spacer (1)" plane through (0, 0, 36.2) normal (0, 0, 1) x (1, 0, 0)
  line L0 (17.5, 11.55) -> (19.5, 11.55)
  line L1 (19.5, 11.55) -> (19.5, 12.25)
  line L2 (19.5, 12.25) -> (17.5, 12.25)
  line L3 (17.5, 12.25) -> (17.5, 11.55)
ref_plane "WorkPlane261" through (0, 0, 33.7) normal (0, 0, 1) x (1, 0, 0)
sketch "OLED flush flexible holder 0.6 PETG (2)" plane through (0, 0, 33.7) normal (0, 0, 1) x (1, 0, 0)
  line L0 (45.5, -24.15) -> (49.5, -24.15)
  line L1 (49.5, -24.15) -> (49.5, -23.55)
  line L2 (49.5, -23.55) -> (45.5, -23.55)
  line L3 (45.5, -23.55) -> (45.5, -24.15)
ref_plane "WorkPlane262" through (0, 0, 33.8) normal (0, 0, 1) x (1, 0, 0)
sketch "OLED flush lower capture ledge (2)" plane through (0, 0, 33.8) normal (0, 0, 1) x (1, 0, 0)
  line L0 (45.5, -24.15) -> (49.5, -24.15)
  line L1 (49.5, -24.15) -> (49.5, -22.95)
  line L2 (49.5, -22.95) -> (45.5, -22.95)
  line L3 (45.5, -22.95) -> (45.5, -24.15)
ref_plane "WorkPlane263" through (0, 0, 36.2) normal (0, 0, 1) x (1, 0, 0)
sketch "OLED flush upper datum spacer (2)" plane through (0, 0, 36.2) normal (0, 0, 1) x (1, 0, 0)
  line L0 (46.5, -23.25) -> (48.5, -23.25)
  line L1 (48.5, -23.25) -> (48.5, -22.55)
  line L2 (48.5, -22.55) -> (46.5, -22.55)
  line L3 (46.5, -22.55) -> (46.5, -23.25)
ref_plane "WorkPlane264" through (0, 0, 33.7) normal (0, 0, 1) x (1, 0, 0)
sketch "OLED flush flexible holder 0.6 PETG (3)" plane through (0, 0, 33.7) normal (0, 0, 1) x (1, 0, 0)
  line L0 (45.5, 12.55) -> (49.5, 12.55)
  line L1 (49.5, 12.55) -> (49.5, 13.15)
  line L2 (49.5, 13.15) -> (45.5, 13.15)
  line L3 (45.5, 13.15) -> (45.5, 12.55)
ref_plane "WorkPlane265" through (0, 0, 33.8) normal (0, 0, 1) x (1, 0, 0)
sketch "OLED flush lower capture ledge (3)" plane through (0, 0, 33.8) normal (0, 0, 1) x (1, 0, 0)
  line L0 (45.5, 11.95) -> (49.5, 11.95)
  line L1 (49.5, 11.95) -> (49.5, 13.15)
  line L2 (49.5, 13.15) -> (45.5, 13.15)
  line L3 (45.5, 13.15) -> (45.5, 11.95)
ref_plane "WorkPlane266" through (0, 0, 36.2) normal (0, 0, 1) x (1, 0, 0)
sketch "OLED flush upper datum spacer (3)" plane through (0, 0, 36.2) normal (0, 0, 1) x (1, 0, 0)
  line L0 (46.5, 11.55) -> (48.5, 11.55)
  line L1 (48.5, 11.55) -> (48.5, 12.25)
  line L2 (48.5, 12.25) -> (46.5, 12.25)
  line L3 (46.5, 12.25) -> (46.5, 11.55)
ref_plane "WorkPlane267" through (0, 0, 31.5) normal (0, 0, 1) x (1, 0, 0)
sketch "Lid guide clear of flush OLED" plane through (0, 0, 31.5) normal (0, 0, 1) x (1, 0, 0)
  line L0 (-23, -10) -> (-22.2, -10)
  line L1 (-22.2, -10) -> (-22.2, 0)
  line L2 (-22.2, 0) -> (-23, 0)
  line L3 (-23, 0) -> (-23, -10)
extrude "Lid guide clear of flush OLED (1)" add sketch "Lid guide clear of flush OLED" along normal blind 6.5 bodies 2
ref_plane "WorkPlane268" through (0, 0, 31.5) normal (0, 0, 1) x (1, 0, 0)
sketch "Lid guide clear of flush OLED (1)" plane through (0, 0, 31.5) normal (0, 0, 1) x (1, 0, 0)
  line L0 (49.91, -10) -> (50.36, -10)
  line L1 (50.36, -10) -> (50.36, 0)
  line L2 (50.36, 0) -> (49.91, 0)
  line L3 (49.91, 0) -> (49.91, -10)
extrude "Lid guide clear of flush OLED (2)" add sketch "Lid guide clear of flush OLED (1)" along normal blind 6.5 bodies 2
move_body "Main PCB mounting level from USB C bottom 12 mm USER" bodies 3 7 8 9 10 11 31 to x (1, 0, 0) y (0, 1, 0) z (0, 0, 1) at (0, 0, 2.37)
move_body "Radio level from SMA bottom 26 mm USER" bodies 5 30 to x (1, 0, 0) y (0, 1, 0) z (0, 0, 1) at (0, 0, -6.455)
move_body "Switch above radio PCB 0.5 clearance USER" bodies 6 to x (1, 0, 0) y (0, 1, 0) z (0, 0, 1) at (0, 0, 7.595)
ref_plane "WorkPlane269" through (0, 0, 11.5) normal (0, 0, 1) x (1, 0, 0)
sketch "PCB support extension from measured USB height" plane through (0, 0, 11.5) normal (0, 0, 1) x (1, 0, 0)
  line L0 (-20.5, -37) -> (-17.5, -37)
  line L1 (-17.5, -37) -> (-17.5, -34.4)
  line L2 (-17.5, -34.4) -> (-20.5, -34.4)
  line L3 (-20.5, -34.4) -> (-20.5, -37)
extrude "PCB support extension from measured USB height (1)" add sketch "PCB support extension from measured USB height" along normal blind 2.37 bodies 1
ref_plane "WorkPlane270" through (0, 0, 11.5) normal (0, 0, 1) x (1, 0, 0)
sketch "PCB support extension from measured USB height (1)" plane through (0, 0, 11.5) normal (0, 0, 1) x (1, 0, 0)
  line L0 (-20.5, 23.9) -> (-17.5, 23.9)
  line L1 (-17.5, 23.9) -> (-17.5, 26.52)
  line L2 (-17.5, 26.52) -> (-20.5, 26.52)
  line L3 (-20.5, 26.52) -> (-20.5, 23.9)
extrude "PCB support extension from measured USB height (2)" add sketch "PCB support extension from measured USB height (1)" along normal blind 2.37 bodies 1
ref_plane "WorkPlane271" through (0, 0, 15.67) normal (0, 0, 1) x (1, 0, 0)
sketch "Main PCB edge retainer corrected height" plane through (0, 0, 15.67) normal (0, 0, 1) x (1, 0, 0)
  line L0 (-20, -36.9) -> (-18, -36.9)
  line L1 (-18, -36.9) -> (-18, -34.9)
  line L2 (-18, -34.9) -> (-20, -34.9)
  line L3 (-20, -34.9) -> (-20, -36.9)
extrude "Main PCB edge retainer corrected height (1)" add sketch "Main PCB edge retainer corrected height" along normal blind 0.6 bodies 1
ref_plane "WorkPlane272" through (0, 0, 15.67) normal (0, 0, 1) x (1, 0, 0)
sketch "Main PCB edge retainer corrected height (1)" plane through (0, 0, 15.67) normal (0, 0, 1) x (1, 0, 0)
  line L0 (-20, 24.4) -> (-18, 24.4)
  line L1 (-18, 24.4) -> (-18, 26.42)
  line L2 (-18, 26.42) -> (-20, 26.42)
  line L3 (-20, 26.42) -> (-20, 24.4)
extrude "Main PCB edge retainer corrected height (2)" add sketch "Main PCB edge retainer corrected height (1)" along normal blind 0.6 bodies 1
ref_plane "WorkPlane273" through (0, 0, 11.5) normal (0, 0, 1) x (1, 0, 0)
sketch "PCB support extension from measured USB height (2)" plane through (0, 0, 11.5) normal (0, 0, 1) x (1, 0, 0)
  line L0 (44.5, -37) -> (47.5, -37)
  line L1 (47.5, -37) -> (47.5, -34.4)
  line L2 (47.5, -34.4) -> (44.5, -34.4)
  line L3 (44.5, -34.4) -> (44.5, -37)
extrude "PCB support extension from measured USB height (3)" add sketch "PCB support extension from measured USB height (2)" along normal blind 2.37 bodies 1
ref_plane "WorkPlane274" through (0, 0, 11.5) normal (0, 0, 1) x (1, 0, 0)
sketch "PCB support extension from measured USB height (3)" plane through (0, 0, 11.5) normal (0, 0, 1) x (1, 0, 0)
  line L0 (44.5, 23.9) -> (47.5, 23.9)
  line L1 (47.5, 23.9) -> (47.5, 26.52)
  line L2 (47.5, 26.52) -> (44.5, 26.52)
  line L3 (44.5, 26.52) -> (44.5, 23.9)
extrude "PCB support extension from measured USB height (4)" add sketch "PCB support extension from measured USB height (3)" along normal blind 2.37 bodies 1
ref_plane "WorkPlane275" through (0, 0, 15.67) normal (0, 0, 1) x (1, 0, 0)
sketch "Main PCB edge retainer corrected height (2)" plane through (0, 0, 15.67) normal (0, 0, 1) x (1, 0, 0)
  line L0 (45, -36.9) -> (47, -36.9)
  line L1 (47, -36.9) -> (47, -34.9)
  line L2 (47, -34.9) -> (45, -34.9)
  line L3 (45, -34.9) -> (45, -36.9)
extrude "Main PCB edge retainer corrected height (3)" add sketch "Main PCB edge retainer corrected height (2)" along normal blind 0.6 bodies 1
ref_plane "WorkPlane276" through (0, 0, 15.67) normal (0, 0, 1) x (1, 0, 0)
sketch "Main PCB edge retainer corrected height (3)" plane through (0, 0, 15.67) normal (0, 0, 1) x (1, 0, 0)
  line L0 (45, 24.4) -> (47, 24.4)
  line L1 (47, 24.4) -> (47, 26.42)
  line L2 (47, 26.42) -> (45, 26.42)
  line L3 (45, 26.42) -> (45, 24.4)
extrude "Main PCB edge retainer corrected height (4)" add sketch "Main PCB edge retainer corrected height (3)" along normal blind 0.6 bodies 1
ref_plane "WorkPlane277" through (51.5, 0, 0) normal (1, 0, 0) x (0, 1, 0)
sketch "SMA neat whole collar corrected height" plane through (51.5, 0, 0) normal (1, 0, 0) x (0, 0, -1)
  circle A0 centre (-26.045, 17) radius 4.6
extrude "SMA neat whole collar corrected height (1)" add sketch "SMA neat whole collar corrected height" along normal blind 0.9316 bodies 1
ref_plane "WorkPlane278" through (52.5316, 0, 0) normal (1, 0, 0) x (0, 1, 0)
sketch "SMA round opening bottom 26 mm from assembly USER" plane through (52.5316, 0, 0) normal (1, 0, 0) x (0, 0, -1)
  circle A0 centre (-26.045, 17) radius 3.4
extrude "SMA round opening bottom 26 mm from assembly USER (1)" cut sketch "SMA round opening bottom 26 mm from assembly USER" against normal blind 3 bodies 1
ref_plane "WorkPlane279" through (52.5316, 0, 0) normal (1, 0, 0) x (0, 1, 0)
sketch "USB C PCB slit corrected measured height" plane through (52.5316, 0, 0) normal (1, 0, 0) x (0, 0, -1)
  line L0 (-11.67, -27.19) -> (-11.67, -9.29)
  line L1 (-11.67, -9.29) -> (-13.67, -9.29)
  line L2 (-13.67, -9.29) -> (-13.67, -27.19)
  line L3 (-13.67, -27.19) -> (-11.67, -27.19)
extrude "USB C PCB slit corrected measured height (1)" cut sketch "USB C PCB slit corrected measured height" against normal blind 3 bodies 1
ref_plane "WorkPlane280" through (52.5316, 0, 0) normal (1, 0, 0) x (0, 1, 0)
sketch "USB C opening bottom 12 mm from assembly USER" plane through (52.5316, 0, 0) normal (1, 0, 0) x (0, 0, -1)
  line L0 (-8.67, -22.64) -> (-8.67, -13.84)
  line L1 (-8.67, -13.84) -> (-8.97, -13.54)
  line L2 (-8.97, -13.54) -> (-11.77, -13.54)
  line L3 (-11.77, -13.54) -> (-12.07, -13.84)
  line L4 (-12.07, -13.84) -> (-12.07, -22.64)
  line L5 (-12.07, -22.64) -> (-11.77, -22.94)
  line L6 (-11.77, -22.94) -> (-8.97, -22.94)
  line L7 (-8.97, -22.94) -> (-8.67, -22.64)
extrude "USB C opening bottom 12 mm from assembly USER (1)" cut sketch "USB C opening bottom 12 mm from assembly USER" against normal blind 3 bodies 1
ref_plane "WorkPlane281" through (-25.1, 0, 0) normal (1, 0, 0) x (0, 1, 0)
sketch "ESP PCB slit raised with main PCB" plane through (-25.1, 0, 0) normal (1, 0, 0) x (0, 0, -1)
  line L0 (-18.27, -32.44) -> (-18.27, -4.04)
  line L1 (-18.27, -4.04) -> (-20.27, -4.04)
  line L2 (-20.27, -4.04) -> (-20.27, -32.44)
  line L3 (-20.27, -32.44) -> (-18.27, -32.44)
ref_plane "WorkPlane282" through (-25.1, 0, 0) normal (1, 0, 0) x (0, 1, 0)
sketch "ESP micro USB opening raised with main PCB" plane through (-25.1, 0, 0) normal (1, 0, 0) x (0, 0, -1)
  line L0 (-19.17, -22.74) -> (-19.17, -13.74)
  line L1 (-19.17, -13.74) -> (-19.87, -13.04)
  line L2 (-19.87, -13.04) -> (-23.07, -13.04)
  line L3 (-23.07, -13.04) -> (-23.77, -13.74)
  line L4 (-23.77, -13.74) -> (-23.77, -22.74)
  line L5 (-23.77, -22.74) -> (-23.07, -23.44)
  line L6 (-23.07, -23.44) -> (-19.87, -23.44)
  line L7 (-19.87, -23.44) -> (-19.17, -22.74)
ref_plane "WorkPlane283" through (0, 27.62, 0) normal (0, 1, 0) x (0, 0, 1)
sketch "Switch aperture above radio corrected height" plane through (0, 27.62, 0) normal (0, 1, 0) x (1, 0, 0)
  line L0 (23.3, -23.145) -> (36.7, -23.145)
  line L1 (36.7, -23.145) -> (36.7, -32.045)
  line L2 (36.7, -32.045) -> (23.3, -32.045)
  line L3 (23.3, -32.045) -> (23.3, -23.145)
extrude "Switch aperture above radio corrected height (1)" cut sketch "Switch aperture above radio corrected height" against normal blind 2 bodies 1
ref_plane "WorkPlane284" through (0, 0, 30.2) normal (0, 0, 1) x (1, 0, 0)
sketch "PETG clip relocated clear of switch" plane through (0, 0, 30.2) normal (0, 0, 1) x (1, 0, 0)
  line L0 (40.4, 24.82) -> (45.6, 24.82)
  line L1 (45.6, 24.82) -> (45.6, 25.62)
  line L2 (45.6, 25.62) -> (40.4, 25.62)
  line L3 (40.4, 25.62) -> (40.4, 24.82)
extrude "PETG clip relocated clear of switch (1)" add sketch "PETG clip relocated clear of switch" along normal blind 7.8 bodies 2
ref_plane "WorkPlane285" through (40.4, 0, 0) normal (1, 0, 0) x (0, 1, 0)
sketch "Latch ramp relocated clear of switch" plane through (40.4, 0, 0) normal (1, 0, 0) x (0, 0, -1)
  line L0 (-30.2, 25.62) -> (-30.85, 26.27)
  line L1 (-30.85, 26.27) -> (-31.1, 26.27)
  line L2 (-31.1, 26.27) -> (-31.75, 25.62)
  line L3 (-31.75, 25.62) -> (-30.2, 25.62)
extrude "Latch ramp relocated clear of switch (1)" add sketch "Latch ramp relocated clear of switch" along normal blind 5.2 bodies 2
ref_plane "WorkPlane286" through (0, 0, 29.6) normal (0, 0, 1) x (1, 0, 0)
sketch "Local clip reinforcement relocated" plane through (0, 0, 29.6) normal (0, 0, 1) x (1, 0, 0)
  line L0 (39.5, 25.92) -> (46.5, 25.92)
  line L1 (46.5, 25.92) -> (46.5, 26.42)
  line L2 (46.5, 26.42) -> (39.5, 26.42)
  line L3 (39.5, 26.42) -> (39.5, 25.92)
extrude "Local clip reinforcement relocated (1)" add sketch "Local clip reinforcement relocated" along normal blind 4.4 bodies 1
ref_plane "WorkPlane287" through (0, 27.62, 0) normal (0, 1, 0) x (0, 0, 1)